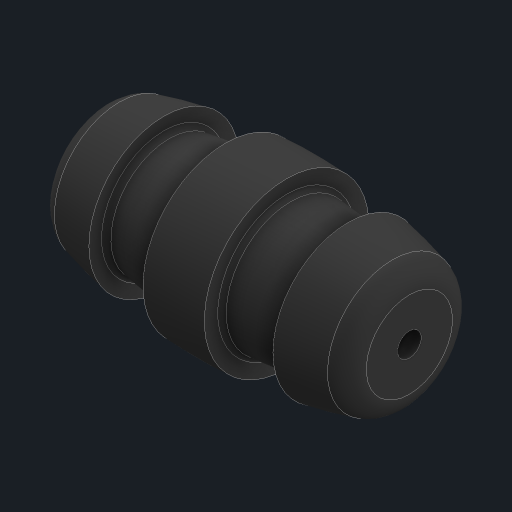
# Autodesk Inventor part: Rolete
Saved by Autodesk Inventor 2024.3 (Build 283343000, 343)
## iProperties
Created: 2025-01-03
Part Number: Rolete
Material: ABS plástico
Document SubType Name: Modeling
Designer: Cliente
Density: 1.23652 g/cm^3
Appearance: Borracha - Preta
Mass: 8.169 g
Surface Area: 26.3694 cm^2
Volume: 6.58158 cm^3
Author: Cliente
Autodesk Inventor part; units mm, degrees
ref_plane "YZ Plane" through (0, 0, 0) normal (1, 0, 0) x (0, 1, 0)
ref_plane "XZ Plane" through (0, 0, 0) normal (0, 1, 0) x (-1, 0, 0)
ref_plane "XY Plane" through (0, 0, 0) normal (0, 0, 1) x (1, 0, 0)
sketch "Esboço1" plane through (0, 0, 0) normal (0, 0, 1) x (1, 0, 0)
  circle A0 centre (0, 0) radius 59.5
  line L0 (0, 0) -> (0, 50)
  line L1 (-17.5, 50) -> (17.5, 50)
  line L2 (-17.5, 50) -> (-17.5, 56.8683)
  line L3 (17.5, 50) -> (17.5, 56.8683)
  line L4 (-17.5, 51.35) -> (17.5, 51.35)
  line L5 (-10.5, 58.5662) -> (-10.5, 51.35)
  line L6 (-3.5, 51.35) -> (-3.5, 59.397)
  line L7 (3.5, 59.397) -> (3.5, 51.35)
  line L8 (10.5, 58.5662) -> (10.5, 51.35)
  circle A1 centre (0, 0) radius 57.5
  point P0 (10.5, 56.5332)
  point P1 (3.5, 57.3934)
  point P2 (-3.5, 57.3934)
  point P3 (-10.5, 56.5332)
  dimension "d0" = 119
  dimension "d1" = 50
  dimension "d2" = 35
  dimension "d3" = 1.35
  dimension "d5" = 7
  dimension "d6" = 7
  dimension "d7" = 7
  dimension "d8" = 7
  dimension "d9" = 7
  dimension "d10" = 2
  constraints: 18 end point, 6 point on circle, 6 point on line, 3 parallel, 3 perpendicular, 2 centre point, 2 vertical, 1 coincident, 1 horizontal, 1 midpoint
  measures "d0" diameter of A0
  measures "d1" distance of L0.end L0.start
  measures "d2" distance of L1.start L1.end
  measures "d3" distance between parallel lines of L1 L4
  measures "d5" distance between parallel lines of L5 L6
  measures "d6" distance between parallel lines of L8 L7
  measures "d7" distance between parallel lines of L2 L5
  measures "d8" distance between parallel lines of L3 L8
  measures "d9" distance between parallel lines of L7 L6
  measures "d10" radial gap between concentric circles of A0 A1
revolve "Revolução1" add sketch "Esboço1" angle 360 about axis through (-17.5, 50, 0) along (1, 0, 0) contours L3 A1 L8 A0 | A0 L5 A1 L2 | L3 L4 L8 A1 | A1 L5 L4 L2 | L7 A1 L6 A0 | L8 L4 L7 A1 | A1 L6 L4 L5 | L7 L4 L6 A1
fillet "Arredondamento1" radius 2.6 2 edges at (17.5, 43.1317, 0) (-17.5, 43.1317, 0)
fillet "Arredondamento2" radius 0.5 4 edges at (-10.5, 43.4668, 0) (-3.5, 42.6066, 0) (3.5, 42.6066, 0) (10.5, 43.4668, 0)
equation "\"d6\" = d5"
equation "\"d8\" = d7"
